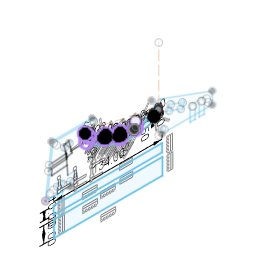
46sp_r3_left (Autodesk Fusion 360 design; units mm, degrees)
Autodesk Fusion 360 part; units mm, degrees
sketch "keypad" plane through (0, 0, 0) normal (1, 0, 0) x (0, 1, 0)
  line L0 (140, 0) -> (140, 99.4072) construction
  line L1 (140, 30) -> (140.9078, 24.5754)
  line L2 (140.9078, 24.5754) -> (112.2562, 19.7808)
  line L3 (112.2562, 19.7808) -> (111.3484, 25.2054)
  line L4 (111.3484, 25.2054) -> (140, 30)
  line L5 (111.3484, 25.2054) -> (110.8213, 19.7307)
  line L6 (110.8213, 19.7307) -> (91.859, 21.5565)
  line L7 (91.859, 21.5565) -> (92.3861, 27.0312)
  line L8 (92.3861, 27.0312) -> (111.3484, 25.2054)
  line L9 (140.5777, 26.548) -> (111.9261, 21.7534)
  line L10 (111.0129, 21.7215) -> (92.0506, 23.5473)
  line L11 (92.3861, 27.0312) -> (90.46, 21.8795)
  line L12 (90.46, 21.8795) -> (72.6164, 28.551)
  line L13 (72.6164, 28.551) -> (74.5425, 33.7027)
  line L14 (74.5425, 33.7027) -> (92.3861, 27.0312)
  line L15 (91.1604, 23.7529) -> (73.3168, 30.4243)
  line L16 (74.5425, 33.7027) -> (71.3486, 29.225)
  line L17 (71.3486, 29.225) -> (47.6986, 46.0945)
  line L18 (47.6986, 46.0945) -> (50.8924, 50.5721)
  line L19 (50.8924, 50.5721) -> (74.5425, 33.7027)
  line L20 (48.86, 47.7227) -> (72.51, 30.8533)
  line L21 (50.8924, 50.5721) -> (140, 30) construction
  line L22 (133.096, 28.8447) -> (134.0038, 23.4201) construction
  line L23 (53.3974, 42.0295) -> (56.5913, 46.5072) construction
  line L24 (91.859, 21.5565) -> (90.9005, 11.6026) construction
  line L25 (50.8924, 50.5721) -> (51.4041, 47.5146) construction
  line L26 (48.86, 47.7227) -> (51.9175, 48.2343) construction
  circle A0 centre (51.1483, 49.0434) radius 1.55
  circle A1 centre (50.3887, 47.9785) radius 1.55
  line L27 (140, 30) -> (138.1998, 27.4762) construction
  line L28 (140.5777, 26.548) -> (138.0539, 28.3482) construction
  circle A2 centre (139.0999, 28.7381) radius 1.55
  circle A3 centre (139.3158, 27.4481) radius 1.55
  line L29 (111.0129, 21.7215) -> (111.9261, 21.7534) construction
  line L30 (111.3484, 25.2054) -> (111.4182, 23.2066) construction
  circle A4 centre (111.4182, 23.2066) radius 1.55
  line L31 (92.0506, 23.5473) -> (91.1604, 23.7529) construction
  line L32 (92.3861, 27.0312) -> (91.9362, 25.0825) construction
  circle A5 centre (91.9362, 25.0825) radius 1.55
  line L33 (72.51, 30.8533) -> (73.3168, 30.4243) construction
  line L34 (74.5425, 33.7027) -> (73.6036, 31.9368) construction
  circle A6 centre (73.6036, 31.9368) radius 1.55
  dimension "d19" = 5.5
  dimension "d20" = 29.05
  dimension "d21" = 5.5
  dimension "d22" = 19.05
  dimension "d23" = 3.5
  dimension "d24" = 3.5
  dimension "d25" = 5.5
  dimension "d26" = 19.05
  dimension "d27" = 3.5
  dimension "d28" = 5.5
  dimension "d29" = 29.05
  dimension "d30" = 3.5
  dimension "d31" = 15
  dimension "d32" = 15
  dimension "d33" = 15
  dimension "d34" = 77
  dimension "d35" = 7
  dimension "d36" = 7
  dimension "d39" = 10
  dimension "d64" = 30
  dimension "d118" = 3.1
  dimension "d119" = 45
  dimension "d120" = 3.1
  dimension "d121" = 45
  dimension "d122" = 3.1
  dimension "d123" = 3.1
  dimension "d124" = 45
  dimension "d125" = 45
  dimension "d128" = 2
  dimension "d129" = 3.1
  dimension "d130" = 2
  dimension "d131" = 3.1
  dimension "d132" = 2
  dimension "d133" = 3.1
  dimension "d174" = 140
  constraint perpendicular L1 L2
  constraint parallel L1 L3
  constraint parallel L2 L4
  constraint coincident L0 L1.start
  constraint perpendicular L5 L6
  constraint parallel L5 L7
  constraint parallel L6 L8
  constraint coincident L1 L9.start
  constraint coincident L3 L9.end
  constraint perpendicular L3 L9
  constraint coincident L5 L10.start
  constraint coincident L7 L10.end
  constraint perpendicular L7 L10
  constraint perpendicular L11 L12
  constraint parallel L11 L13
  constraint parallel L12 L14
  constraint coincident L11 L15.start
  constraint coincident L13 L15.end
  constraint perpendicular L13 L15
  constraint perpendicular L16 L17
  constraint parallel L16 L18
  constraint parallel L17 L19
  constraint coincident L18 L20.start
  constraint coincident L16 L20.end
  constraint perpendicular L16 L20
  constraint coincident L4 L22.start
  constraint coincident L2 L22.end
  constraint perpendicular L2 L22
  constraint coincident L17 L23.start
  constraint coincident L19 L23.end
  constraint perpendicular L19 L23
  constraint perpendicular L6 L24
  constraint vertical L0
  constraint coincident L25.end A0
  constraint coincident L18.end A0
  constraint coincident L26.end A1
  constraint coincident L20.start A1
  constraint coincident L27.end A2
  constraint coincident L1.start A2
  constraint coincident L28.end A3
  constraint coincident L9.start A3
  constraint perpendicular L29 L30
  constraint coincident L30.end A4.centre
  constraint perpendicular L31 L32
  constraint coincident L32.end A5.centre
  constraint perpendicular L33 L34
  constraint coincident L34.end A6.centre
  measures "d19" distance of L1.start L1.end
  measures "d20" distance of L1.start L3.end
  measures "d21" distance of L3.end L5.end
  measures "d22" distance of L3.end L7.end
  measures "d23" distance of L4 L9
  measures "d24" distance of L8 L10
  measures "d25" distance of L7.end L11.end
  measures "d26" distance of L7.end L13.end
  measures "d27" distance of L14 L15
  measures "d28" distance of L13.end L16.end
  measures "d29" distance of L13.end L18.end
  measures "d30" distance of L19 L20
  measures "d31" angle of L13 L16
  measures "d32" angle of L7 L11
  measures "d33" angle of L3 L5
  measures "d34" angle of L0 L21
  measures "d35" distance of L1 L22
  measures "d36" distance of L18 L23
  measures "d39" distance of L6.end L24.end
  measures "d64" distance of L0.start L1.start
  measures "d118" distance of L20.start L26.end
  measures "d119" angle of L20 L26
  measures "d120" distance of L18.end L25.end
  measures "d121" angle of L19 L25
  measures "d122" distance of L1.start L27.end
  measures "d123" distance of L9.start L28.end
  measures "d124" angle of L9 L28
  measures "d125" angle of L4 L27
  measures "d128" distance of L3.end L30.end
  measures "d129" diameter of A4
  measures "d130" distance of L7.end L32.end
  measures "d131" diameter of A5
  measures "d132" distance of L13.end L34.end
  measures "d133" diameter of A6
  measures "d174" distance of origin L0.start
sketch "inside" plane through (0, 0, 0) normal (1, 0, 0) x (0, 1, 0)
  line L0 (111.3484, 25.2054) -> (140, 30)
  line L1 (133.096, 28.8447) -> (132.846, 30.3387)
  line L2 (134.0038, 23.4201) -> (136.7515, 7)
  line L3 (133.096, 28.8447) -> (140, 30)
  line L4 (140.9078, 24.5754) -> (134.0038, 23.4201)
  line L5 (140.9078, 24.5754) -> (140, 30)
  line L6 (56.5913, 46.5072) -> (61.9124, 53.9671)
  line L7 (50.8924, 50.5721) -> (74.5425, 33.7027)
  line L8 (56.5913, 46.5072) -> (50.8924, 50.5721)
  line L9 (50.8924, 50.5721) -> (47.6986, 46.0945)
  line L10 (47.6986, 46.0945) -> (53.3974, 42.0295)
  line L11 (37.925, 14) -> (37.925, 7)
  line L12 (10.0212, 60) -> (55.1501, 60)
  line L13 (136.7515, 7) -> (143.7515, 7)
  line L14 (143.7515, 7) -> (143.7515, 3)
  line L15 (37.925, 7) -> (30.925, 7)
  line L16 (30.925, 7) -> (30.925, 3)
  line L17 (53.3974, 42.0295) -> (50.4939, 37.959)
  line L18 (50.4939, 37.959) -> (31.9126, 37.959)
  line L19 (60.7379, 58.4282) -> (59.3763, 59.0631)
  line L20 (27.59, 14) -> (37.925, 14)
  line L21 (142.1436, 38.0721) -> (201.4364, 16.4969)
  line L22 (140.9078, 24.5754) -> (150.2723, 21.0675) construction
  line L23 (25.4939, 37.959) -> (27.59, 14)
  line L24 (28.765, 49.7059) -> (22.7763, 48.1012)
  line L25 (22.7763, 48.1012) -> (25.4939, 37.959)
  line L26 (28.765, 49.7059) -> (31.9126, 37.959)
  line L27 (25.4939, 37.959) -> (4.4346, 36.1165)
  line L28 (25.4939, 37.959) -> (26.0168, 31.9818)
  line L29 (26.0168, 31.9818) -> (3.687, 30.0282)
  line L30 (7.0891, 30.3258) -> (7.6992, 23.3525)
  line L31 (7.6992, 23.3525) -> (26.6269, 25.0084)
  line L32 (206.0428, 9.9189) -> (206.0428, 5)
  line L33 (13.5602, 58) -> (54.7067, 58)
  line L34 (2.9793, 7.8531) -> (8.5974, 53.6093)
  line L35 (60.6464, 56.2641) -> (58.9329, 57.0631)
  line L36 (0.6887, 5.6093) -> (7.0436, 57.3656)
  line L37 (28.765, 49.7059) -> (22.7763, 48.1012)
  line L38 (22.7763, 48.1012) -> (26.6586, 33.6123)
  line L39 (26.6586, 33.6123) -> (32.6473, 35.217)
  line L40 (32.6473, 35.217) -> (28.765, 49.7059)
  line L41 (25.7989, 34.4723) -> (3.9985, 32.565)
  circle A0 centre (51.1483, 49.0434) radius 1.55
  circle A1 centre (139.0999, 28.7381) radius 1.55
  line L42 (27.925, 0) -> (20.925, 0)
  line L43 (20.925, 0) -> (14.725, 0)
  line L44 (14.725, 0) -> (14.725, 10.5)
  line L45 (14.725, 10.5) -> (20.925, 10.5)
  line L46 (20.925, 10.5) -> (20.925, 0)
  line L47 (20.925, 0) -> (14.725, 0)
  line L48 (14.725, 0) -> (14.725, -5)
  line L49 (14.725, -5) -> (20.925, -5)
  line L50 (20.925, -5) -> (20.925, 0)
  line L51 (9.9271, 0) -> (14.725, 0)
  arc A2 (142.1436, 38.0721) -> (132.846, 30.3387) centre (139.75, 31.494) ccw
  arc A3 (201.0428, 0) -> (206.0428, 5) centre (201.0428, 5) ccw
  arc A4 (206.0428, 9.9189) -> (201.4364, 16.4969) centre (199.0428, 9.9189) ccw
  arc A5 (143.7515, 3) -> (146.7515, 0) centre (146.7515, 3) ccw
  circle A6 centre (143.7515, 5.45) radius 1.55
  arc A7 (27.925, 0) -> (30.925, 3) centre (27.925, 3) ccw
  circle A8 centre (30.925, 5.45) radius 1.55
  arc A9 (59.3763, 59.0631) -> (55.1501, 60) centre (55.1501, 50) ccw
  arc A10 (58.9329, 57.0631) -> (54.7067, 58) centre (54.7067, 48) ccw
  arc A11 (61.9124, 53.9671) -> (60.7379, 58.4282) centre (59.47, 55.7092) ccw
  line L52 (56.5913, 46.5072) -> (61.4294, 53.29)
  arc A12 (61.4294, 53.29) -> (60.6464, 56.2641) centre (59.8012, 54.4514) ccw
  arc A13 (13.5602, 58) -> (8.5974, 53.6093) centre (13.5602, 53) ccw
  arc A14 (10.0212, 60) -> (7.0436, 57.3656) centre (10.0212, 57) ccw
  arc A15 (2.9793, 7.8531) -> (9.9271, 0) centre (9.9271, 7) ccw
  line L53 (5.6515, 0) -> (14.725, 0)
  arc A16 (0.6887, 5.6093) -> (5.6515, 0) centre (5.6515, 5) ccw
  line L54 (150.2723, 21.0675) -> (152.3923, 26.8938)
  line L55 (152.3923, 26.8938) -> (171.6566, 19.884)
  line L56 (171.6566, 19.884) -> (169.5366, 14.0577)
  line L57 (169.5366, 14.0577) -> (150.2723, 21.0675)
  circle A17 centre (14.725, 7.95) radius 2.55
  circle A18 centre (20.925, 7.95) radius 2.55
  circle A19 centre (23.4363, 45.6381) radius 2.55
  circle A20 centre (29.425, 47.2428) radius 2.55
  line L58 (146.7515, 0) -> (201.0428, 0)
  circle A21 centre (169.2603, 20.756) radius 2.55
  circle A22 centre (167.1403, 14.9297) radius 2.55
  circle A23 centre (154.7886, 26.0218) radius 2.55
  circle A24 centre (152.6603, 20.173) radius 2.55
  line L59 (184.8428, -5) -> (178.6428, -5)
  line L60 (178.6428, -5) -> (178.6428, 10.5)
  line L61 (181.1928, 13.05) -> (182.2928, 13.05)
  line L62 (184.8428, 10.5) -> (184.8428, -5)
  line L63 (189.8428, -5) -> (196.0428, -5)
  line L64 (196.0428, -5) -> (196.0428, 10.5)
  line L65 (193.4928, 13.05) -> (192.3928, 13.05)
  line L66 (189.8428, 10.5) -> (189.8428, -5)
  line L67 (184.8428, 13.05) -> (189.8428, 13.05) construction
  arc A25 (181.1928, 13.05) -> (178.6428, 10.5) centre (181.1928, 10.5) ccw
  arc A26 (184.8428, 10.5) -> (182.2928, 13.05) centre (182.2928, 10.5) ccw
  arc A27 (196.0428, 10.5) -> (193.4928, 13.05) centre (193.4928, 10.5) ccw
  arc A28 (192.3928, 13.05) -> (189.8428, 10.5) centre (192.3928, 10.5) ccw
  point P0 (133.096, 28.8447)
  point P1 (206.0428, 14.8208)
  point P2 (134.0038, 23.4201)
  point P3 (140.9078, 24.5754)
  point P4 (56.5913, 46.5072)
  point P5 (47.6986, 46.0945)
  point P6 (53.3974, 42.0295)
  point P7 (7.3671, 60)
  point P8 (143.7515, 0)
  point P9 (30.925, 0)
  point P10 (57.3671, 60)
  point P11 (130.8651, 42.176)
  point P12 (206.0428, 0)
  point P13 (51.1483, 49.0434)
  point P14 (139.0999, 28.7381)
  dimension "d57" = 7
  dimension "d58" = 7
  dimension "d59" = 5
  dimension "d67" = 7
  dimension "d70" = 25
  dimension "d71" = 50
  dimension "d72" = 155
  dimension "d79" = 10
  dimension "d91" = 95
  dimension "d93" = 10.5
  dimension "d94" = 6.2
  dimension "d95" = 105
  dimension "d98" = 6
  dimension "d99" = 7
  dimension "d100" = 19
  dimension "d114" = 80
  dimension "d116" = 7
  dimension "d168" = 2
  dimension "d172" = 2
  dimension "d197" = 15
  dimension "d201" = 3.5
  dimension "d220" = 10
  dimension "d221" = 6.2
  dimension "d222" = 10.5
  dimension "d223" = 5
  dimension "d226" = 7
  dimension "d227" = 5
  dimension "d228" = 7
  dimension "d229" = 3
  dimension "d230" = 3.1
  dimension "d231" = 3
  dimension "d232" = 7
  dimension "d233" = 3.1
  dimension "d234" = 10
  dimension "d235" = 10
  dimension "d236" = 3
  dimension "d237" = 2
  dimension "d238" = 5
  dimension "d239" = 3
  dimension "d240" = 7
  dimension "d241" = 5
  dimension "d251" = 6.2
  dimension "d252" = 20.5
  dimension "d257" = 7
  dimension "d258" = 5.1
  dimension "d259" = 5.1
  dimension "d260" = 5.1
  dimension "d261" = 5.1
  dimension "d271" = 5.1
  dimension "d272" = 5.1
  dimension "d273" = 5.1
  dimension "d274" = 5.1
  dimension "d275" = 18.05
  dimension "d276" = 5
  dimension "d277" = 13.05
  dimension "d278" = 2.55
  dimension "d279" = 2.55
  dimension "d280" = 2.55
  dimension "d281" = 2.55
  constraint coincident P0 L1.start
  constraint perpendicular L0 L1
  constraint coincident P2 L2.start
  constraint parallel L1 L2
  constraint coincident L0.end L3.end
  constraint coincident P3 L4.start
  constraint coincident P4 L6.start
  constraint perpendicular L6 L7
  constraint coincident L7.start L8.end
  constraint coincident P5 L9.end
  constraint coincident P6 L10.end
  constraint perpendicular L11 L15
  constraint vertical L16
  constraint vertical L14
  constraint perpendicular L10 L17
  constraint horizontal L18
  constraint perpendicular L11 L20
  constraint horizontal L12
  constraint horizontal L20
  constraint perpendicular L24 L26
  constraint perpendicular L24 L25
  constraint perpendicular L23 L27
  constraint perpendicular L27 L28
  constraint parallel L27 L29
  constraint coincident L29 L30.start
  constraint perpendicular L29 L30
  constraint coincident L23 L31.end
  constraint perpendicular L23 L31
  constraint horizontal L17.end L23.start
  constraint vertical L32
  constraint horizontal L13
  constraint horizontal L33
  constraint parallel L19 L35
  constraint parallel L34 L36
  constraint perpendicular L37 L38
  constraint parallel L37 L39
  constraint parallel L38 L40
  constraint coincident L28 L41.start
  constraint coincident L36 L41.end
  constraint perpendicular L23 L41
  constraint coincident P13 A0.centre
  constraint coincident L7.start A0
  constraint coincident P14 A1.centre
  constraint coincident L0.end A1
  constraint perpendicular L16 L42
  constraint horizontal L43
  constraint vertical L44
  constraint horizontal L45
  constraint vertical L46
  constraint horizontal L47
  constraint vertical L48
  constraint horizontal L49
  constraint vertical L50
  constraint perpendicular L44 L51
  constraint coincident L1 P11
  constraint coincident P11 L21
  constraint tangent L1 A2
  constraint tangent L21 A2
  constraint coincident P12 L32
  constraint tangent L32 A3
  constraint coincident P1 L21
  constraint coincident P1 L32
  constraint tangent L21 A4
  constraint tangent L32 A4
  constraint coincident P8 L14
  constraint tangent L14 A5
  constraint coincident L13.end A6
  constraint coincident P9 L16
  constraint coincident P9 L42
  constraint tangent L16 A7
  constraint tangent L42 A7
  constraint coincident L15.end A8
  constraint coincident P10 L19
  constraint coincident L12 P10
  constraint tangent L19 A9
  constraint tangent L12 A9
  constraint tangent L35 A10
  constraint tangent L33 A10
  constraint tangent L6 A11
  constraint tangent L19 A11
  constraint tangent L35 A12
  constraint tangent L52 A12
  constraint tangent L34 A13
  constraint tangent L33 A13
  constraint coincident P7 L12
  constraint coincident P7 L36
  constraint tangent L12 A14
  constraint tangent L36 A14
  constraint tangent L34 A15
  constraint tangent L51 A15
  constraint perpendicular L48 L53
  constraint tangent L53 A16
  constraint tangent L36 A16
  constraint perpendicular L54 L55
  constraint parallel L54 L56
  constraint parallel L55 L57
  constraint parallel L21 L55
  constraint coincident L44.end A17
  constraint coincident L45.end A18
  constraint coincident L24.end A19
  constraint coincident L24.start A20
  constraint tangent A3 L58
  constraint coincident L55.end A21
  constraint coincident L56.end A22
  constraint coincident L54.end A23
  constraint coincident L22.end A24
  constraint horizontal L59
  constraint vertical L60
  constraint horizontal L61
  constraint vertical L62
  constraint horizontal L63
  constraint vertical L64
  constraint horizontal L65
  constraint vertical L66
  constraint horizontal L67
  constraint tangent L60 A25
  constraint tangent L61 A25
  constraint coincident L67.start L61
  constraint coincident L67.start L62
  constraint tangent L61 A26
  constraint tangent L62 A26
  constraint tangent L64 A27
  constraint tangent L65 A27
  constraint coincident L67.end L66
  constraint coincident L67.end L65
  constraint tangent L66 A28
  constraint tangent L65 A28
  measures "d57" distance of L2.end L13.end
  measures "d58" distance of L11.end L15.end
  measures "d59" distance of P6 L17.end
  measures "d67" distance of L11.end L11.start
  measures "d70" distance of L17.end L23.start
  measures "d71" distance of P7 P10
  measures "d72" angle of L12 L19
  measures "d79" distance of L22.end P3
  measures "d91" angle of L20 L23
  measures "d93" distance of L23.start L24.end
  measures "d94" distance of L24.start L24.end
  measures "d95" angle of L18 L26
  measures "d98" distance of L23.start L28.end
  measures "d99" distance of L30.start L30.end
  measures "d100" distance of L23 L30
  measures "d114" distance of P1 P11
  measures "d116" distance of L13.end P8
  measures "d168" distance of L12 L33
  measures "d172" distance of L19 L35
  measures "d197" distance of L24.start L39.end
  measures "d201" distance of L27 L41
  measures "d220" distance of P9 L42.end
  measures "d221" distance of L42.end L43.end
  measures "d222" distance of L42.end L45.end
  measures "d223" distance of L42.end L49.end
  measures "d226" radius of A2
  measures "d227" radius of A3
  measures "d228" radius of A4
  measures "d229" radius of A5
  measures "d230" diameter of A6
  measures "d231" radius of A7
  measures "d232" distance of L15 L42
  measures "d233" diameter of A8
  measures "d234" radius of A9
  measures "d235" radius of A10
  measures "d236" radius of A11
  measures "d237" radius of A12
  measures "d238" radius of A13
  measures "d239" radius of A14
  measures "d240" radius of A15
  measures "d241" radius of A16
  measures "d251" distance of L22.end L54.end
  measures "d252" distance of L22.end L56.end
  measures "d257" distance of L21 L55
  measures "d258" diameter of A17
  measures "d259" diameter of A18
  measures "d260" diameter of A19
  measures "d261" diameter of A20
  measures "d271" diameter of A21
  measures "d272" diameter of A22
  measures "d273" diameter of A23
  measures "d274" diameter of A24
  measures "d275" distance of L59.start L67.start
  measures "d276" distance of L67.start L67.end
  measures "d277" distance of L58 L67
  measures "d278" radius of A25
  measures "d279" radius of A26
  measures "d280" radius of A27
  measures "d281" radius of A28
sketch "side" plane through (0, 0, 0) normal (1, 0, 0) x (0, 1, 0)
  line L0 (10.0212, 60) -> (55.3845, 60)
  line L1 (133.096, 28.8447) -> (132.846, 30.3387)
  line L2 (136.7515, 7) -> (125.1982, 76.04) construction
  line L3 (59.311, 59.6108) -> (111.9994, 49.0614)
  line L4 (147.6398, 38.3967) -> (201.6645, 16.5747)
  line L5 (142.1436, 38.0721) -> (201.4364, 16.4969)
  line L6 (206.0428, 10.0842) -> (206.0428, 2)
  line L7 (204.0428, 0) -> (5.6515, 0)
  line L8 (0.6887, 5.6093) -> (7.0436, 57.3656)
  arc A0 (0.6887, 5.6093) -> (5.6515, 0) centre (5.6515, 5) ccw
  arc A1 (10.0212, 60) -> (7.0436, 57.3656) centre (10.0212, 57) ccw
  arc A2 (204.0428, 0) -> (206.0428, 2) centre (204.0428, 2) ccw
  arc A3 (206.0428, 10.0842) -> (201.6645, 16.5747) centre (199.0428, 10.0842) ccw
  arc A4 (59.311, 59.6108) -> (55.3845, 60) centre (55.3845, 40) ccw
  arc A5 (147.6398, 38.3967) -> (111.9994, 49.0614) centre (72.7342, -147.0464) ccw
  point P0 (7.3671, 60)
  point P1 (57.3671, 60)
  point P2 (206.0428, 14.8208)
  point P3 (136.7515, 7)
  dimension "d73" = 70
  dimension "d74" = 2
  dimension "d242" = 5
  dimension "d243" = 3
  dimension "d244" = 2
  dimension "d245" = 7
  dimension "d246" = 20
  dimension "d247" = 200
  constraint coincident P3 L2.start
  constraint parallel L1 L2
  constraint vertical L6
  constraint perpendicular L6 L7
  constraint tangent L8 A0
  constraint tangent L7 A0
  constraint tangent L8 A1
  constraint tangent L0 A1
  constraint tangent L6 A2
  constraint tangent L7 A2
  constraint tangent L4 A3
  constraint tangent L6 A3
  constraint tangent L3 A4
  constraint tangent L0 A4
  constraint tangent L3 A5
  constraint tangent L4 A5
  measures "d73" distance of P3 L2.end
  measures "d74" angle of L4 L5
  measures "d242" radius of A0
  measures "d243" radius of A1
  measures "d244" radius of A2
  measures "d245" radius of A3
  measures "d246" radius of A4
  measures "d247" radius of A5
sketch "keypad_side" plane through (0, 0, 0) normal (1, 0, 0) x (0, 1, 0)
  line L0 (47.6986, 46.0945) -> (50.8924, 50.5721)
  line L1 (47.6986, 46.0945) -> (43.628, 48.998) construction
  line L2 (140, 30) -> (140.9078, 24.5754)
  line L3 (140.9078, 24.5754) -> (145.8392, 25.4007) construction
  line L4 (144.6839, 32.3047) -> (47.6929, 54.6968)
  line L5 (144.6839, 32.3047) -> (145.8392, 25.4007)
  line L6 (47.6929, 54.6968) -> (43.628, 48.998)
  line L7 (43.628, 48.998) -> (43.628, 43.998)
  line L8 (145.8392, 25.4007) -> (145.8392, 20.4007)
  line L9 (50.8924, 50.5721) -> (92.3861, 27.0312) construction
  line L10 (110.8213, 19.7307) -> (112.2562, 19.7808) construction
  line L11 (91.859, 21.5565) -> (90.46, 21.8795) construction
  line L12 (72.6164, 28.551) -> (71.3486, 29.225) construction
  line L13 (71.9825, 28.888) -> (69.6351, 24.4733) construction
  line L14 (91.1595, 21.718) -> (90.0347, 16.8462) construction
  line L15 (111.5387, 19.7557) -> (111.7132, 14.7588) construction
  line L16 (43.628, 43.998) -> (69.6351, 24.4733)
  line L17 (69.6351, 24.4733) -> (90.0347, 16.8462)
  line L18 (90.0347, 16.8462) -> (111.7132, 14.7588)
  line L19 (111.7132, 14.7588) -> (145.8392, 20.4007)
  circle A0 centre (70.8323, 26.7248) radius 2.55
  circle A1 centre (90.6083, 19.3308) radius 2.55
  circle A2 centre (111.6242, 17.3072) radius 2.55
  line L20 (145.8392, 20.4007) -> (141.9496, 23.6993) construction
  circle A3 centre (143.8944, 22.05) radius 2.55
  circle A4 centre (143.3257, 24.9704) radius 2.55
  line L21 (144.6839, 32.3047) -> (140.9692, 28.8102) construction
  circle A5 centre (142.8265, 30.5574) radius 2.55
  line L22 (43.628, 43.998) -> (48.1901, 46.2778) construction
  circle A6 centre (45.909, 45.1379) radius 2.55
  circle A7 centre (45.704, 47.5172) radius 2.55
  line L23 (47.6929, 54.6968) -> (49.4998, 49.9276) construction
  circle A8 centre (48.5964, 52.3122) radius 2.55
  line L24 (111.3484, 25.2054) -> (92.3861, 27.0312) construction
  line L25 (74.5425, 33.7027) -> (92.3861, 27.0312)
  line L26 (92.3861, 27.0312) -> (74.5425, 33.7027)
  point P0 (47.6986, 46.0945)
  point P1 (140, 30)
  point P2 (91.859, 21.5565)
  point P3 (92.3861, 27.0312)
  point P4 (110.8213, 19.7307)
  point P5 (112.2562, 19.7808)
  point P6 (90.46, 21.8795)
  point P7 (72.6164, 28.551)
  point P8 (71.3486, 29.225)
  point P9 (111.3484, 25.2054)
  point P10 (74.5425, 33.7027)
  dimension "d134" = 5
  dimension "d137" = 5
  dimension "d141" = 5
  dimension "d142" = 5
  dimension "d143" = 5
  dimension "d144" = 5
  dimension "d145" = 5
  dimension "d146" = 7
  dimension "d147" = 7
  dimension "d179" = 5.1
  dimension "d180" = 5.1
  dimension "d181" = 5.1
  dimension "d182" = 5.1
  dimension "d183" = 49.7
  dimension "d184" = 5.1
  dimension "d185" = 5.1
  dimension "d186" = 56.25
  dimension "d187" = 5.1
  dimension "d188" = 63.45
  dimension "d189" = 5.1
  dimension "d190" = 5.1
  dimension "d191" = 56.25
  constraint coincident P0 L0.start
  constraint perpendicular L0 L1
  constraint coincident L2.end L3.start
  constraint perpendicular L2 L3
  constraint perpendicular L3 L5
  constraint perpendicular L1 L6
  constraint vertical L7
  constraint vertical L8
  constraint coincident L0.end L9.start
  constraint coincident P3 L9.end
  constraint coincident P4 L10.start
  constraint coincident P5 L10.end
  constraint coincident P2 L11.start
  constraint coincident P6 L11.end
  constraint coincident P7 L12.start
  constraint coincident P8 L12.end
  constraint midpoint L12 L13.start
  constraint perpendicular L12 L13
  constraint midpoint L11 L14.start
  constraint perpendicular L11 L14
  constraint midpoint L10 L15.start
  constraint perpendicular L10 L15
  constraint coincident L13.end A0
  constraint coincident L14.end A1
  constraint coincident L15.end A2
  constraint coincident L20.end A3
  constraint coincident L8.end A3
  constraint coincident L3.end A4
  constraint coincident L21.end A5
  constraint coincident L4.start A5
  constraint coincident L22.end A6
  constraint coincident L7.end A6
  constraint coincident L1.end A7
  constraint coincident L23.end A8
  constraint coincident L4.end A8
  constraint coincident P9 L24.start
  constraint coincident P10 L25.start
  measures "d134" distance of P0 L1.end
  measures "d137" distance of L2.end L3.end
  measures "d141" distance of L1.end L7.end
  measures "d142" distance of L3.end L8.end
  measures "d143" distance of L13.start L13.end
  measures "d144" distance of L14.start L14.end
  measures "d145" distance of L15.start L15.end
  measures "d146" distance of L3.end L4.start
  measures "d147" distance of L1.end L4.end
  measures "d179" diameter of A0
  measures "d180" diameter of A1
  measures "d181" diameter of A2
  measures "d182" distance of L8.end L20.end
  measures "d183" angle of L8 L20
  measures "d184" diameter of A4
  measures "d185" distance of L4.start L21.end
  measures "d186" angle of L4 L21
  measures "d187" distance of L7.end L22.end
  measures "d188" angle of L16 L22
  measures "d189" diameter of A7
  measures "d190" distance of L4.end L23.end
  measures "d191" angle of L4 L23
extrude "Extrude1" add sketch "keypad" along normal mid plane 134 contours L1 L9 A2 A3 | L1 A2 A3 | L3 L4 L9 A2 A3 A4 | L1 L4 A2 A3 | L3 L9 A4 | L3 L5 A4 | L5 L7 L8 L10 A4 A5 | L5 L10 A4 | L11 L13 L14 L15 A5 A6 | L7 L10 A5 | L11 L15 A5 | L16 L19 L20 A0 A1 A6 | L13 L15 A6 | L16 L20 A6 | L18 L19 A0 A1 | L18 L20 A0 A1 | L18 A0 A1 picked at (139.1552, 28.3844) picked at (111.6644, 23.75) picked at (111.3589, 24.9055) picked at (111.1332, 23.7312) picked at (92.3159, 25.5432) picked at (91.7966, 25.663) picked at (74.0911, 32.2822) picked at (73.619, 32.5336) picked at (50.4736, 48.3659) makes body 1 in component "keypad"
extrude "Extrude1'" add sketch "keypad_side" along normal blind 4 from surface at 63 separate body contours L0 L7 A6 A7 | L0 A6 A7 | L7 A6 A7 | L4 L5 L6 L16 L17 L18 L19 A0 A1 A2 A3 A4 A5 A6 A7 A8 | L7 L16 A6 A7 | L4 L6 A8 | L16 L17 A0 | L4 L5 A5 | L17 L18 A1 | L8 A3 A4 | L8 A3 A4 | L18 L19 A2 | L8 L19 A3 A4 | A3 A4 picked at (45.6405, 46.7608) makes body 2 in component "keypad_side_r"
extrude "Extrude1''" add sketch "keypad_side" against normal blind 4 from surface at -63 separate body contours L0 L7 A6 A7 | L0 A6 A7 | L7 A6 A7 | L4 L5 L6 L16 L17 L18 L19 A0 A1 A2 A3 A4 A5 A6 A7 A8 | L7 L16 A6 A7 | L4 L6 A8 | L16 L17 A0 | L4 L5 A5 | L17 L18 A1 | L8 A3 A4 | L8 A3 A4 | L18 L19 A2 | L8 L19 A3 A4 | A3 A4 picked at (45.6405, 46.7608) makes body 3 in component "keypad_side_l"
extrude "Extrude1'''" add sketch "side" along normal blind 12 from surface at 63 separate body makes body 4 in component "side_r"
extrude "Extrude1''''" add sketch "side" against normal blind 12 from surface at -63 separate body makes body 5 in component "side_l"
extrude "Extrude1'''''" add sketch "inside" along normal mid plane 126 separate body contours L0 L1 L2 L3 L4 L5 L13 L14 L21 L32 A1 A2 A3 A4 A5 A6 L58 L60 L61 L62 L64 L65 L66 A25 A26 A27 A28 makes body 6 in component "inside_fw"
extrude "Extrude1''''''" add sketch "inside" along normal blind 63 separate body contours L6 L7 L8 L9 L10 L17 L18 L24 L25 L26 L27 L33 L34 L35 L37 L38 L40 A0 A10 L52 A12 A13 A19 A20 | L6 L12 L19 L27 L33 L34 L35 L36 A9 A10 A11 A12 A13 A14 | L27 L34 L36 L41 | L23 L27 L28 L34 L41 | L23 L28 L29 L34 L41 | L29 L34 L36 L41 | L29 L34 L36 A15 L53 A16 | L11 L15 L16 L20 L23 L29 L30 L31 L34 L42 L44 L45 L46 L51 A7 A8 A15 L53 A17 A18 | L23 L29 L30 L31 makes body 7 in component "inside_bw_a"
extrude "Extrude1'''''''" add sketch "inside" against normal blind 63 separate body contours L6 L7 L8 L9 L10 L17 L18 L24 L25 L26 L27 L33 L34 L35 L37 L38 L40 A0 A10 L52 A12 A13 A19 A20 | L23 L27 L28 L34 L41 | L23 L28 L29 L34 L41 | L11 L15 L16 L20 L23 L29 L30 L31 L34 L42 L44 L45 L46 L51 A7 A8 A15 L53 A17 A18 | L23 L29 L30 L31 makes body 8 in component "inside_bw_b"
extrude "Extrude2" cut sketch "keypad" along normal through all from surface at 63 contours L1 L9 A2 A3 | L9 A3 | L1 A2 A3 | L1 A2 A3 | L1 A2 A3 | L3 L4 L9 A2 A3 A4 | L1 L4 A2 A3 | L1 A2 A3 | L3 L9 A4 | L3 L5 A4 | L4 A2 | L3 L5 A4 | L5 L7 L8 L10 A4 A5 | L5 L10 A4 | L7 L11 A5 | L11 L13 L14 L15 A5 A6 | L7 L10 A5 | L7 L11 A5 | L11 L15 A5 | L13 L16 A6 | L16 L19 L20 A0 A1 A6 | L13 L15 A6 | L13 L16 A6 | L16 L20 A6 | L18 L19 A0 A1 | L19 A0 | L18 A0 A1 | L20 A1 | L18 L20 A0 A1 | L18 A0 A1 | L18 A0 A1 | L18 A0 A1 picked at (111.6644, 23.75) picked at (111.1332, 23.7312) picked at (92.3159, 25.5432) picked at (91.7966, 25.663) picked at (74.0911, 32.2822) picked at (73.619, 32.5336) bodies 2 in component "keypad_side_r"
extrude "Extrude2'" cut sketch "keypad" along normal through all from surface at -67 contours L1 L9 A2 A3 | L9 A3 | L1 A2 A3 | L1 A2 A3 | L1 A2 A3 | L3 L4 L9 A2 A3 A4 | L1 L4 A2 A3 | L1 A2 A3 | L3 L9 A4 | L3 L5 A4 | L4 A2 | L3 L5 A4 | L5 L7 L8 L10 A4 A5 | L5 L10 A4 | L7 L11 A5 | L11 L13 L14 L15 A5 A6 | L7 L10 A5 | L7 L11 A5 | L11 L15 A5 | L13 L16 A6 | L16 L19 L20 A0 A1 A6 | L13 L15 A6 | L13 L16 A6 | L16 L20 A6 | L18 L19 A0 A1 | L19 A0 | L18 A0 A1 | L20 A1 | L18 L20 A0 A1 | L18 A0 A1 | L18 A0 A1 | L18 A0 A1 picked at (111.6644, 23.75) picked at (111.1332, 23.7312) picked at (92.3159, 25.5432) picked at (91.7966, 25.663) picked at (74.0911, 32.2822) picked at (73.619, 32.5336) bodies 3 in component "keypad_side_l"
extrude "Extrude2''" cut sketch "keypad_side" sketch "inside" along normal blind 6 of sketch 2 contours L58 L63 L64 L66 | L58 L64 L65 L66 A27 A28 | L58 L59 L60 L62 | L58 L60 L61 L62 A25 A26 | L24 L25 L26 L37 L38 L39 L40 A19 A20 | L26 L40 A20 | L26 L40 A20 | L25 L38 A19 | L25 L38 A19 | L43 L44 L45 L46 L47 A17 A18 | L43 L47 L48 L49 L50 | L44 A17 | L44 A17 | L46 A18 | L46 A18 | L57 A24 | L54 L55 L56 L57 A21 A22 A23 A24 | L57 A24 | L55 A23 | L55 A23 | L57 A22 | L57 A22 | L55 A21 | L55 A21 start surface through (63, 0, 0) normal (-1, 0, 0) bodies 4 in component "side_r"
extrude "Extrude2'''" cut sketch "keypad_side" sketch "inside" against normal blind 6 of sketch 2 contours L58 L63 L64 L66 | L58 L64 L65 L66 A27 A28 | L58 L59 L60 L62 | L58 L60 L61 L62 A25 A26 | L24 L25 L26 L37 L38 L39 L40 A19 A20 | L26 L40 A20 | L26 L40 A20 | L25 L38 A19 | L25 L38 A19 | L43 L44 L45 L46 L47 A17 A18 | L43 L47 L48 L49 L50 | L44 A17 | L44 A17 | L46 A18 | L46 A18 | L57 A24 | L54 L55 L56 L57 A21 A22 A23 A24 | L57 A24 | L55 A23 | L55 A23 | L57 A22 | L57 A22 | L55 A21 | L55 A21 start surface through (-63, 0, 0) normal (1, 0, 0) bodies 5 in component "side_l"
sketch "bone" plane through (0, 0, 0) normal (1, 0, 0) x (0, 1, 0)
  line L0 (10, -10) -> (144, -10)
  line L1 (144, -10) -> (144, -20)
  line L2 (144, -20) -> (10, -20)
  line L3 (10, -20) -> (10, -10)
  line L4 (10.4696, -25) -> (144.4696, -25)
  line L5 (144.4696, -25) -> (144.4696, -45)
  line L6 (144.4696, -45) -> (10.4696, -45)
  line L7 (10.4696, -45) -> (10.4696, -25)
  line L8 (138.6051, 26.2179) -> (111.4716, 21.6773)
  line L9 (48.86, 47.7227) -> (72.51, 30.8533)
  line L10 (48.86, 47.7227) -> (72.8852, 30.5857)
  line L11 (91.592, 23.5915) -> (111.4716, 21.6773)
  line L12 (72.8852, 30.5857) -> (91.592, 23.5915)
  line L13 (134.0038, 23.4201) -> (138.9352, 24.2453)
  line L14 (138.9352, 24.2453) -> (138.6051, 26.2179)
  line L15 (134.0038, 23.4201) -> (134.829, 18.4887)
  line L16 (92.3861, 27.0312) -> (91.9362, 25.0825)
  line L17 (92.3861, 27.0312) -> (90.0037, 16.7121) construction
  line L18 (74.5425, 33.7027) -> (73.6036, 31.9368)
  line L19 (74.5425, 33.7027) -> (69.5705, 24.3517) construction
  line L20 (134.829, 18.4887) -> (111.718, 14.6212)
  line L21 (111.718, 14.6212) -> (90.0037, 16.7121)
  line L22 (90.0037, 16.7121) -> (69.5705, 24.3517)
  line L23 (53.3974, 42.0295) -> (50.4939, 37.959)
  line L24 (111.0129, 21.7215) -> (92.0506, 23.5473)
  line L25 (91.1604, 23.7529) -> (73.3168, 30.4243)
  line L26 (69.5705, 24.3517) -> (50.4939, 37.959)
  line L27 (50.4939, 37.959) -> (53.3974, 42.0295)
  line L28 (53.3974, 42.0295) -> (49.3268, 44.9331)
  line L29 (49.3268, 44.9331) -> (50.4882, 46.5613)
  line L30 (113.4442, 22.0074) -> (112.915, 25.1694)
  line L31 (109.4808, 21.869) -> (109.7881, 25.0602)
  line L32 (112.915, 25.1694) -> (109.7881, 25.0602)
  line L33 (111.718, 14.6212) -> (111.1945, 29.6121) construction
  line L34 (91.859, 21.5565) -> (92.3861, 27.0312)
  line L35 (93.5828, 23.3998) -> (93.8901, 26.591)
  line L36 (89.7186, 24.2919) -> (90.8414, 27.2949)
  line L37 (93.8901, 26.591) -> (90.8414, 27.2949)
  line L38 (74.7585, 29.8853) -> (75.8813, 32.8882)
  line L39 (71.2569, 31.7471) -> (73.1187, 34.3571)
  line L40 (75.8813, 32.8882) -> (73.1187, 34.3571)
  point P0 (48.86, 47.7227)
  point P1 (134.0038, 23.4201)
  point P2 (111.3484, 25.2054)
  point P3 (92.3861, 27.0312)
  point P4 (74.5425, 33.7027)
  dimension "d248" = 134
  dimension "d249" = 10
  dimension "d250" = 20
  dimension "d286" = 5
  dimension "d287" = 5
  dimension "d293" = 5
  dimension "d299" = 10.5
  dimension "d301" = 2
  dimension "d302" = 2
  dimension "d303" = 10.5
  dimension "d304" = 2
  dimension "d305" = 2
  dimension "d306" = 2
  dimension "d307" = 2
  dimension "d308" = 10.5
  constraint horizontal L0
  constraint vertical L1
  constraint horizontal L2
  constraint vertical L3
  constraint horizontal L4
  constraint vertical L5
  constraint horizontal L6
  constraint vertical L7
  constraint equal L0 L4
  constraint coincident P0 L9.start
  constraint parallel L9 L10
  constraint coincident P1 L13.start
  constraint perpendicular L13 L15
  constraint coincident P3 L16.start
  constraint parallel L16 L17
  constraint coincident P4 L18.start
  constraint parallel L18 L19
  constraint parallel L21 L24
  constraint parallel L22 L25
  constraint parallel L9 L26
  constraint perpendicular L27 L28
  constraint coincident L10 L29.end
  constraint coincident L8 L30.start
  constraint perpendicular L8 L30
  constraint coincident L24 L31.start
  constraint coincident L11 L31.start
  constraint perpendicular L24 L31
  constraint perpendicular L32 L33
  constraint coincident L24 L35.start
  constraint coincident L11 L35.start
  constraint perpendicular L24 L35
  constraint coincident L25 L36.start
  constraint coincident L12 L36.start
  constraint perpendicular L25 L36
  constraint perpendicular L17 L37
  constraint coincident L25 L38.start
  constraint coincident L12 L38.start
  constraint perpendicular L25 L38
  constraint coincident L9 L39.start
  constraint perpendicular L9 L39
  constraint perpendicular L19 L40
  measures "d248" distance of L0.start L0.end
  measures "d249" distance of L0.start L2.end
  measures "d250" distance of L4.start L6.end
  measures "d286" distance of P1 L13.end
  measures "d287" distance of P1 L15.end
  measures "d293" distance of L23.start L28.end
  measures "d299" distance of L20.end L32
  measures "d301" distance of L11.start L35
  measures "d302" distance of L11.start L36
  measures "d303" distance of L17.end L37
  measures "d304" distance of L8.end L30
  measures "d305" distance of L8.end L31
  measures "d306" distance of L10.end L38
  measures "d307" distance of L10.end L39
  measures "d308" distance of L19.end L40
component "keypad" placed x (1, 0, 0) y (0, 1, 0) z (0, 0, 1) at (0, 0, 0)
component "keypad_side_r" placed x (1, 0, 0) y (0, 1, 0) z (0, 0, 1) at (0, 0, 0)
component "keypad_side_l" placed x (1, 0, 0) y (0, 1, 0) z (0, 0, 1) at (0, 0, 0)
component "side_r" placed x (1, 0, 0) y (0, 1, 0) z (0, 0, 1) at (0, 0, 0)
component "side_l" placed x (1, 0, 0) y (0, 1, 0) z (0, 0, 1) at (0, 0, 0)
component "inside_fw" placed x (1, 0, 0) y (0, 1, 0) z (0, 0, 1) at (0, 0, 0)
component "inside_bw_a" placed x (1, 0, 0) y (0, 1, 0) z (0, 0, 1) at (0, 0, 0)
component "inside_bw_b" placed x (1, 0, 0) y (0, 1, 0) z (0, 0, 1) at (0, 0, 0)
equation "d20 = 19.05 mm + 3 mm + 7 mm"
equation "d34 = 90 deg - 13 deg"
equation "d148 = 126 mm + 8 mm"
equation "d152 = ( 126 * 0.5 ) * 1 mm"
equation "d155 = ( -126 * 0.5 ) * 1 mm"
equation "d158 = ( 126 * 0.5 ) * 1 mm"
equation "d161 = ( -126 * 0.5 ) * 1 mm"
equation "d166 = ( 126 * 0.5 ) * 1 mm"
equation "d170 = ( -126 * 0.5 ) * 1 mm"
equation "d183 = ( 99.4 * 0.5 ) * 1 deg"
equation "d186 = ( 112.5 * 0.5 ) * 1 deg"
equation "d188 = ( 126.9 * 0.5 ) * 1 deg"
equation "d191 = ( 112.5 * 0.5 ) * 1 deg"
equation "d248 = 126 mm + 8 mm"
equation "d275 = 15.500 mm + ( 5.1 * 0.5 ) * 1 mm"
equation "d277 = 10.5 mm + ( 5.1 * 0.5 ) * 1 mm"
